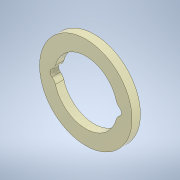
# Autodesk Inventor part: 24-10-25-washer-Lawrence-A2213271-v1
Saved by Autodesk Inventor 2022 (Build 260153000, 153)
## iProperties
Created: 2024-10-26
Part Number: 24-10-25-washer-Lawrence-A2213271-v1
Material: Generic
Document SubType Name: Modeling
Designer: Dell
Density: 1 g/cm^3
Appearance: Smooth - Ash
Author: Dell
Autodesk Inventor part; units mm, degrees
ref_plane "YZ Plane" through (0, 0, 0) normal (1, 0, 0) x (0, 1, 0)
ref_plane "XZ Plane" through (0, 0, 0) normal (0, 1, 0) x (-1, 0, 0)
ref_plane "XY Plane" through (0, 0, 0) normal (0, 0, 1) x (1, 0, 0)
sketch "Sketch1" plane through (0, 0, 0) normal (0, 0, 1) x (1, 0, 0)
  circle A0 centre (0, 0) radius 11
  line L0 (-7.5, 0) -> (7.5, 0) construction
  arc A1 (-7.5, 1) -> (-7.5, -1) centre (-7.5, 0) ccw
  arc A2 (7.5, -1) -> (7.5, 1) centre (7.5, 0) ccw
  line L1 (7.5, 1) -> (7.433, 1)
  line L2 (-7.433, 1) -> (-7.5, 1)
  line L3 (-7.5, -1) -> (-7.433, -1)
  line L4 (7.433, -1) -> (7.5, -1)
  arc A3 (-7.433, -1) -> (7.433, -1) centre (0, 0) ccw
  arc A4 (7.433, 1) -> (-7.433, 1) centre (0, 0) ccw
  dimension "d0" = 22
  dimension "d2" = 2
  constraints: 12 end point, 8 point on circle, 8 tangent, 5 centre point, 4 parallel, 2 coincident, 1 horizontal, 1 midpoint
  measures "d0" diameter of A0
  measures "d2" diameter of A2
extrude "Extrusion1" add sketch "Sketch1" along normal blind 2
fillet "Fillet1" radius 2 4 edges at (-7.433, 1, 1) (-7.433, -1, 1) (7.433, 1, 1) (7.433, -1, 1)
body "Solid1"
